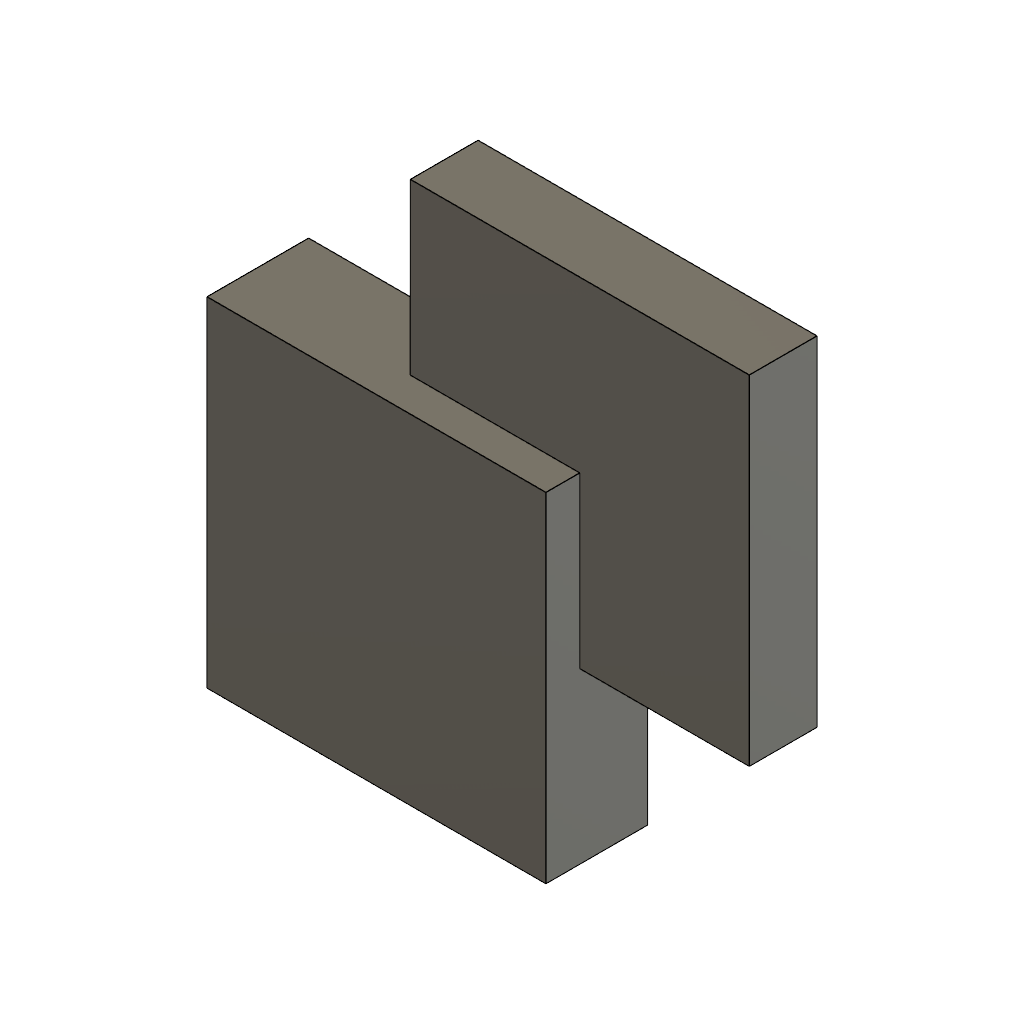
comb_join (Autodesk Fusion 360 design; units mm, degrees)
part number: 2026-11-13-14-45-48-949
Autodesk Fusion 360 part; units mm, degrees
sketch "Sketch1" plane through (0, 0, 0) normal (0, 0, 1) x (1, 0, 0)
  line L0 (0, 0) -> (20, 0)
  line L1 (20, 0) -> (20, 20)
  line L2 (20, 20) -> (0, 20)
  line L3 (0, 20) -> (0, 0)
extrude "Extrude1" add sketch "Sketch1" along normal blind 6 makes body 1
sketch "Sketch2" plane through (0, 0, 0) normal (0, 0, 1) x (1, 0, 0)
  line L0 (10, 10) -> (30, 10)
  line L1 (30, 10) -> (30, 30)
  line L2 (30, 30) -> (10, 30)
  line L3 (10, 30) -> (10, 10)
extrude "Extrude2" add sketch "Sketch2" along normal blind 4 separate body makes body 2
combine "Combine1" operation add target body 1 tool bodies 2
